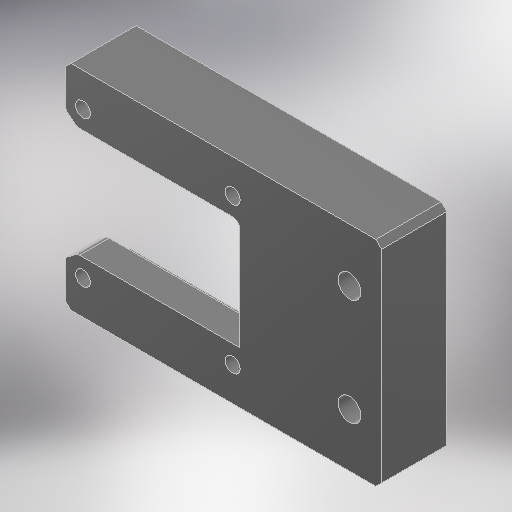
# Autodesk Inventor part: T3.0_servo-mount_bottom
Saved by Autodesk Inventor 2025.3 (Build 293356030, 356C)
## iProperties
Created: 2024-04-22
Part Number: T3.0_servo-mount_bottom
Material: 一般
Document SubType Name: Sheet Metal
Designer: 8326d
Density: 1 g/cm^3
Sheet Metal Rule: Default_mm
Appearance: 滑らか - 黒
Author: 8326d
## iProperties of the stored document T3.0_servo-mount_bottom_3D プリント.ipt
Created: 2024-09-23
Part Number: T3.0_servo-mount_bottom_3D プリント
Material: 一般
Document SubType Name: Modeling
Designer: 8326d
Density: 1 g/cm^3
Appearance: 既定
Author: 8326d
Autodesk Inventor part; units mm, degrees
ref_plane "YZ Plane" through (0, 0, 0) normal (1, 0, 0) x (0, 1, 0)
ref_plane "XZ Plane" through (0, 0, 0) normal (0, 1, 0) x (-1, 0, 0)
ref_plane "XY Plane" through (0, 0, 0) normal (0, 0, 1) x (1, 0, 0)
sketch "スケッチ1" plane through (0, 0, 0) normal (0, 0, 1) x (1, 0, 0)
  line L0 (-17.6925, -15) -> (17.6925, -15)
  line L1 (17.6925, -15) -> (17.6925, 15)
  line L2 (17.6925, 15) -> (-17.6925, 15)
  line L3 (-17.6925, 15) -> (-17.6925, -15)
  line L4 (-17.6925, -15) -> (17.6925, 15) construction
  line L5 (17.6925, -15) -> (-17.6925, 15) construction
  point P0 (0, 0)
  dimension "d0" = 35.385
  dimension "d1" = 30
  measures "d0" distance of L1.end L2.end
  measures "d1" distance of L0.end L1.end
extrude "プレート1" add sketch "スケッチ1" along normal blind 4.15
sketch "スケッチ2" plane through (0, 0, 4.15) normal (0, 0, 1) x (1, 0, 0)
  line L0 (-15.1925, -10.25) -> (5.8075, -10.25) construction
  line L1 (5.8075, -10.25) -> (5.8075, 10.25) construction
  line L2 (5.8075, 10.25) -> (-15.1925, 10.25) construction
  line L3 (-15.1925, 10.25) -> (-15.1925, -10.25) construction
  line L4 (-15.1925, -10.25) -> (5.8075, 10.25) construction
  line L5 (5.8075, -10.25) -> (-15.1925, 10.25) construction
  line L6 (17.6925, 15) -> (17.6925, -15) construction
  line L7 (-17.6925, -15) -> (-17.6925, 15) projected
  point P0 (0, 0)
  point P1 (-4.6925, 0)
  dimension "d3" = 21
  dimension "d4" = 20.5
  dimension "d42" = 2.5
  constraints: 12 end point, 2 midpoint, 2 parallel, 1 horizontal, 1 horizontal alignment, 1 perpendicular
  measures "d3" distance of L2.end L1.end
  measures "d4" distance of L1.end L0.end
  measures "d42" distance between parallel lines of L7 L3
hole "穴1" at (-15.1925, 10.25, 4.15) at (5.8075, 10.25, 4.15) at (5.8075, -10.25, 4.15) at (-15.1925, -10.25, 4.15) direction (0, 0, -1) diameter 2.1 end through all
sketch "スケッチ3" plane through (0, 0, 0) normal (0, 0, -1) x (-1, 0, 0)
  line L0 (-17.6925, -15) -> (-17.6925, 15) projected
  line L1 (17.6925, 15) -> (17.6925, -15) projected
  line L2 (-17.6925, 7.7) -> (17.6925, 7.7)
  line L3 (17.6925, -7.7) -> (-17.6925, -7.7)
  line L4 (-17.6925, 15) -> (17.6925, 15) projected
  line L5 (17.6925, -15) -> (-17.6925, -15) projected
  line L6 (-12.6925, 7.7) -> (-12.6925, -7.7)
  point P0 (0, 0)
  dimension "d43" = 5
  dimension "d88" = 7.7
  dimension "d89" = 7.7
  constraints: 6 end point, 6 point on line, 4 perpendicular
  measures "d43" distance between parallel lines of L0 L6
  measures "d88" distance from line of L3 point (0, 0)
  measures "d89" distance from line of L2 point (0, 0)
extrude "押し出し1" cut sketch "スケッチ3" against normal blind 1.5 contours L6 L2 L1 L3
sketch "スケッチ4" plane through (0, 0, 4.15) normal (0, 0, 1) x (1, 0, 0)
  line L0 (-17.6925, 15) -> (17.6925, 15) projected
  line L1 (17.6925, -15) -> (-17.6925, -15) projected
  circle A0 centre (-23.1925, 0) radius 10.5
  line L2 (17.6925, 15) -> (17.6925, -15) projected
  line L3 (-12.1925, -9.6) -> (-12.1925, 9.6)
  line L4 (6.8075, 9.6) -> (6.8075, -9.6)
  line L5 (6.8075, -9.6) -> (-12.1925, 9.6) construction
  line L6 (-12.1925, -9.6) -> (6.8075, 9.6) construction
  line L7 (-12.1925, 7.7) -> (-16.0539, 7.7)
  line L8 (-16.0539, 7.7) -> (-16.0539, -7.7)
  line L9 (-16.0539, -7.7) -> (-12.1925, -7.7)
  line L10 (-12.1925, -7.7) -> (-12.1925, 7.7)
  line L11 (12.6925, 7.7) -> (-17.6925, 7.7) projected
  line L12 (-17.6925, -7.7) -> (12.6925, -7.7) projected
  line L13 (-17.6925, -7.7) -> (12.6925, -7.7) projected
  line L14 (12.6925, 7.7) -> (-17.6925, 7.7) projected
  line L15 (12.6925, 7.7) -> (-17.6925, 7.7) projected
  point P0 (0, 0)
  point P1 (17.6925, 0)
  point P2 (-2.6925, 0)
  point P3 (-12.1925, 0)
  point P4 (-16.0539, 7.7)
  point P5 (17.6925, 7.7)
  point P6 (-16.0539, 7.7)
  point P7 (-12.1925, -3.3541)
  point P8 (-12.1925, 3.3541)
  point P9 (6.8075, 7.7)
  point P10 (-12.1925, 7.7)
  point P11 (6.8075, -7.7)
  dimension "d18" = 21
  dimension "d17" = 40.885
  dimension "d22" = 19
  dimension "d41" = 11
  constraints: 16 end point, 4 midpoint, 3 horizontal alignment, 3 parallel, 1 collinear, 1 horizontal, 1 perpendicular, 1 point on line, 3 other
  measures "d17" distance from line of L2 point (-23.192, 0)
  measures "d22" distance between parallel lines of L4 L10
  measures "d41" distance from line of point (-23.192, 0) L3
extrude "押し出し2" cut sketch "スケッチ4" against normal through all
fillet "フィレット1" radius 1 5 edges at (-16.0539, -7.7, 2.075) (-16.0539, 7.7, 2.075) (-17.6925, 8.9443, 2.075) (-17.6925, -8.9443, 2.075) (6.8075, 7.7, 2.825)
fillet "フィレット2" radius 1.2 2 edges at (12.6925, 7.7, 0.75) (12.6925, -7.7, 0.75)
sketch "スケッチ12" plane through (17.6925, -15, 0) normal (1, 0, 0) x (0, 0, -1)
  line L0 (-4.15, 30) -> (-4.15, 0) projected
  line L1 (0, 0) -> (-4.15, 0) projected
  line L2 (0, 0) -> (0, 30) projected
  line L3 (0, 30) -> (-4.15, 30) projected
  point P0 (0, 15)
extrude "押し出し7" add sketch "スケッチ12" along normal blind 9
sketch "スケッチ13" plane through (0, 0, 0) normal (0, 0, -1) x (-1, 0, 0)
  line L0 (17.6925, -9.4868) -> (17.6925, -15) projected
  line L1 (17.6925, -15) -> (-26.6925, -15) projected
  line L2 (-12.6925, -6.5) -> (-12.6925, 6.5) projected
  line L3 (-26.6925, -15) -> (-26.6925, 15) projected
  line L4 (17.6925, 15) -> (-26.6925, 15) projected
  line L5 (17.6925, 15) -> (17.6925, 9.4868) projected
  line L6 (17.6925, 12.5) -> (-12.6925, 12.5)
  line L7 (-12.6925, 12.5) -> (-12.6925, 6.5)
  arc A0 (-12.6925, -6.5) -> (-11.4925, -7.7) centre (-11.4925, -6.5) ccw projected
  line L8 (-12.6925, -6.5) -> (-12.6925, -12.5)
  line L9 (-12.6925, -12.5) -> (17.6925, -12.5)
  point P0 (0, 0)
  dimension "d92" = 2.5
  dimension "d93" = 2.5
  constraints: 8 end point, 3 point on line, 2 perpendicular, 1 horizontal, 1 tangent
  measures "d92" distance between parallel lines of L9 L1
  measures "d93" distance between parallel lines of L4 L6
extrude "押し出し8" add sketch "スケッチ13" along normal blind 5
fillet "フィレット4" radius 2 2 edges at (12.6925, -12.5, -2.5) (12.6925, 12.5, -2.5)
sketch "スケッチ14" plane through (0, 0, -5) normal (0, 0, -1) x (-1, 0, 0)
  line L0 (-26.6925, 15) -> (-26.6925, -15) projected
  line L1 (17.6925, 15) -> (-26.6925, 15) projected
  line L2 (-26.6925, -15) -> (17.6925, -15) projected
  line L3 (-22.1925, 15) -> (-22.1925, -15) construction
  point P0 (0, 0)
  point P1 (-22.1925, 7.5)
  point P2 (-22.1925, -7.5)
  dimension "d97" = 4.5
  dimension "d98" = 7.5
  dimension "d99" = 7.5
  constraints: 4 point on line, 2 end point, 1 vertical
  measures "d97" distance between parallel lines of L0 L3
  measures "d98" distance from line of L1 point (-22.193, 7.5)
  measures "d99" distance from line of L2 point (-22.193, -7.5)
hole "穴5" at (22.1925, 7.5, -5) at (22.1925, -7.5, -5) direction (0, 0, 1) diameter 3.2 end through all
sketch "スケッチ15" plane through (0, 0, -5) normal (0, 0, -1) x (-1, 0, 0)
  circle A0 centre (-22.1925, 7.5) radius 1.6 projected
  circle A1 centre (-22.1925, -7.5) radius 1.6 projected
  line L0 (-22.1925, 10.7332) -> (-19.3925, 9.1166)
  line L1 (-19.3925, 9.1166) -> (-19.3925, 5.8834)
  line L2 (-19.3925, 5.8834) -> (-22.1925, 4.2668)
  line L3 (-22.1925, 4.2668) -> (-24.9925, 5.8834)
  line L4 (-24.9925, 5.8834) -> (-24.9925, 9.1166)
  line L5 (-24.9925, 9.1166) -> (-22.1925, 10.7332)
  line L6 (-22.1925, -4.2668) -> (-19.3925, -5.8834)
  line L7 (-19.3925, -5.8834) -> (-19.3925, -9.1166)
  line L8 (-19.3925, -9.1166) -> (-22.1925, -10.7332)
  line L9 (-22.1925, -10.7332) -> (-24.9925, -9.1166)
  line L10 (-24.9925, -9.1166) -> (-24.9925, -5.8834)
  line L11 (-24.9925, -5.8834) -> (-22.1925, -4.2668)
  point P0 (0, 0)
  dimension "d107" = 5.6
  dimension "d108" = 5.6
  constraints: 24 end point, 2 coincident, 2 vertical alignment, 26 other
  measures "d107" distance between parallel lines of L4 L1
  measures "d108" distance between parallel lines of L10 L7
extrude "押し出し9" cut sketch "スケッチ15" against normal blind 5
chamfer "面取り1" distance 0.8 angle 45 4 edges at (-17.6925, 15, -0.425) (-17.6925, -15, -0.425) (26.6925, 15, -0.425) (26.6925, -15, -0.425)
equation "\"d11\" = Thickness"
equation "\"d89\" = d88"
equation "\"d93\" = d92"
equation "\"d99\" = d98"
equation "\"d105\" = Thickness"
equation "\"d108\" = d107"
equation "\"d2\" = Thickness"
equation "\"BendRadius\" = Thickness"
equation "\"BendReliefWidth\" = Thickness"
equation "\"BendReliefDepth\" = 0.5 * Thickness"
equation "\"CornerReliefSize\" = 4 * Thickness"
equation "\"MinimumRemnant\" = 2 * Thickness"
equation "\"TransitionRadius\" = BendRadius"
equation "\"JacobiRadiusSize\" = BendRadius"
equation "\"GapSize\" = Thickness"
equation "\"Thickness\" = 4.15"
